Autodesk Inventor part; units mm, degrees
(part 2 of 2)
  line L501 (103.0341, -6.3552) -> (95.8923, 0.7866)
  line L502 (-87.0362, -54.297) -> (-79.8944, -61.4388)
  line L503 (-79.8944, -61.4388) -> (-72.7527, -54.297)
  line L504 (-79.8944, -47.1552) -> (-87.0362, -54.297)
  line L505 (-72.7527, -54.297) -> (-79.8944, -47.1552)
  line L506 (-79.0459, -46.3067) -> (-71.9041, -53.4485)
  line L507 (-71.9041, -53.4485) -> (-64.7624, -46.3067)
  line L508 (-71.9041, -39.1649) -> (-79.0459, -46.3067)
  line L509 (-64.7624, -46.3067) -> (-71.9041, -39.1649)
  line L510 (-71.0556, -38.3164) -> (-63.9138, -45.4582)
  line L511 (-63.9138, -45.4582) -> (-56.7721, -38.3164)
  line L512 (-63.9138, -31.1746) -> (-71.0556, -38.3164)
  line L513 (-56.7721, -38.3164) -> (-63.9138, -31.1746)
  line L514 (-63.0653, -30.3261) -> (-55.9235, -37.4679)
  line L515 (-55.9235, -37.4679) -> (-48.7817, -30.3261)
  line L516 (-55.9235, -23.1843) -> (-63.0653, -30.3261)
  line L517 (-48.7817, -30.3261) -> (-55.9235, -23.1843)
  line L518 (-55.075, -22.3358) -> (-47.9332, -29.4775)
  line L519 (-47.9332, -29.4775) -> (-40.7914, -22.3358)
  line L520 (-47.9332, -15.194) -> (-55.075, -22.3358)
  line L521 (-40.7914, -22.3358) -> (-47.9332, -15.194)
  line L522 (-47.0847, -14.3455) -> (-39.9429, -21.4872)
  line L523 (-39.9429, -21.4872) -> (-32.8011, -14.3455)
  line L524 (-39.9429, -7.2037) -> (-47.0847, -14.3455)
  line L525 (-32.8011, -14.3455) -> (-39.9429, -7.2037)
  line L526 (-39.0944, -6.3552) -> (-31.9526, -13.4969)
  line L527 (-31.9526, -13.4969) -> (-24.8108, -6.3552)
  line L528 (-31.9526, 0.7866) -> (-39.0944, -6.3552)
  line L529 (-24.8108, -6.3552) -> (-31.9526, 0.7866)
  line L530 (-31.1041, 1.6352) -> (-23.9623, -5.5066)
  line L531 (-23.9623, -5.5066) -> (-16.8205, 1.6352)
  line L532 (-23.9623, 8.7769) -> (-31.1041, 1.6352)
  line L533 (-16.8205, 1.6352) -> (-23.9623, 8.7769)
  line L534 (-23.1138, 9.6255) -> (-15.972, 2.4837)
  line L535 (-15.972, 2.4837) -> (-8.8302, 9.6255)
  line L536 (-15.972, 16.7672) -> (-23.1138, 9.6255)
  line L537 (-8.8302, 9.6255) -> (-15.972, 16.7672)
  line L538 (-15.1235, 17.6158) -> (-7.9817, 10.474)
  line L539 (-7.9817, 10.474) -> (-0.8399, 17.6158)
  line L540 (-7.9817, 24.7575) -> (-15.1235, 17.6158)
  line L541 (-0.8399, 17.6158) -> (-7.9817, 24.7575)
  line L542 (-7.1332, 25.6061) -> (0.0086, 18.4643)
  line L543 (0.0086, 18.4643) -> (7.1504, 25.6061)
  line L544 (0.0086, 32.7478) -> (-7.1332, 25.6061)
  line L545 (7.1504, 25.6061) -> (0.0086, 32.7478)
  line L546 (0.8571, 33.5964) -> (7.9989, 26.4546)
  line L547 (7.9989, 26.4546) -> (15.1407, 33.5964)
  line L548 (7.9989, 40.7382) -> (0.8571, 33.5964)
  line L549 (15.1407, 33.5964) -> (7.9989, 40.7382)
  line L550 (8.8475, 41.5867) -> (15.9892, 34.4449)
  line L551 (15.9892, 34.4449) -> (23.131, 41.5867)
  line L552 (15.9892, 48.7285) -> (8.8475, 41.5867)
  line L553 (23.131, 41.5867) -> (15.9892, 48.7285)
  line L554 (16.8378, 49.577) -> (23.9795, 42.4352)
  line L555 (23.9795, 42.4352) -> (31.1213, 49.577)
  line L556 (23.9795, 56.7188) -> (16.8378, 49.577)
  line L557 (31.1213, 49.577) -> (23.9795, 56.7188)
  line L558 (24.8281, 57.5673) -> (31.9698, 50.4255)
  line L559 (31.9698, 50.4255) -> (39.1116, 57.5673)
  line L560 (31.9698, 64.7091) -> (24.8281, 57.5673)
  line L561 (39.1116, 57.5673) -> (31.9698, 64.7091)
  line L562 (-15.1235, -126.2098) -> (-7.9817, -133.3515)
  line L563 (-7.9817, -133.3515) -> (-0.8399, -126.2098)
  line L564 (-7.9817, -119.068) -> (-15.1235, -126.2098)
  line L565 (-0.8399, -126.2098) -> (-7.9817, -119.068)
  line L566 (-7.1332, -118.2194) -> (0.0086, -125.3612)
  line L567 (0.0086, -125.3612) -> (7.1504, -118.2194)
  line L568 (0.0086, -111.0777) -> (-7.1332, -118.2194)
  line L569 (7.1504, -118.2194) -> (0.0086, -111.0777)
  line L570 (0.8571, -110.2291) -> (7.9989, -117.3709)
  line L571 (7.9989, -117.3709) -> (15.1407, -110.2291)
  line L572 (7.9989, -103.0874) -> (0.8571, -110.2291)
  line L573 (15.1407, -110.2291) -> (7.9989, -103.0874)
  line L574 (8.8475, -102.2388) -> (15.9892, -109.3806)
  line L575 (15.9892, -109.3806) -> (23.131, -102.2388)
  line L576 (15.9892, -95.0971) -> (8.8475, -102.2388)
  line L577 (23.131, -102.2388) -> (15.9892, -95.0971)
  line L578 (16.8378, -94.2485) -> (23.9795, -101.3903)
  line L579 (23.9795, -101.3903) -> (31.1213, -94.2485)
  line L580 (23.9795, -87.1067) -> (16.8378, -94.2485)
  line L581 (31.1213, -94.2485) -> (23.9795, -87.1067)
  line L582 (24.8281, -86.2582) -> (31.9698, -93.4)
  line L583 (31.9698, -93.4) -> (39.1116, -86.2582)
  line L584 (31.9698, -79.1164) -> (24.8281, -86.2582)
  line L585 (39.1116, -86.2582) -> (31.9698, -79.1164)
  line L586 (32.8184, -78.2679) -> (39.9602, -85.4097)
  line L587 (39.9602, -85.4097) -> (47.1019, -78.2679)
  line L588 (39.9602, -71.1261) -> (32.8184, -78.2679)
  line L589 (47.1019, -78.2679) -> (39.9602, -71.1261)
  line L590 (40.8087, -70.2776) -> (47.9505, -77.4194)
  line L591 (47.9505, -77.4194) -> (55.0922, -70.2776)
  line L592 (47.9505, -63.1358) -> (40.8087, -70.2776)
  line L593 (55.0922, -70.2776) -> (47.9505, -63.1358)
  line L594 (48.799, -62.2873) -> (55.9408, -69.4291)
  line L595 (55.9408, -69.4291) -> (63.0825, -62.2873)
  line L596 (55.9408, -55.1455) -> (48.799, -62.2873)
  line L597 (63.0825, -62.2873) -> (55.9408, -55.1455)
  line L598 (56.7893, -54.297) -> (63.9311, -61.4388)
  line L599 (63.9311, -61.4388) -> (71.0728, -54.297)
  line L600 (63.9311, -47.1552) -> (56.7893, -54.297)
  line L601 (71.0728, -54.297) -> (63.9311, -47.1552)
  line L602 (64.7796, -46.3067) -> (71.9214, -53.4485)
  line L603 (71.9214, -53.4485) -> (79.0632, -46.3067)
  line L604 (71.9214, -39.1649) -> (64.7796, -46.3067)
  line L605 (79.0632, -46.3067) -> (71.9214, -39.1649)
  line L606 (72.7699, -38.3164) -> (79.9117, -45.4582)
  line L607 (79.9117, -45.4582) -> (87.0535, -38.3164)
  line L608 (79.9117, -31.1746) -> (72.7699, -38.3164)
  line L609 (87.0535, -38.3164) -> (79.9117, -31.1746)
  line L610 (80.7602, -30.3261) -> (87.902, -37.4679)
  line L611 (87.902, -37.4679) -> (95.0438, -30.3261)
  line L612 (87.902, -23.1843) -> (80.7602, -30.3261)
  line L613 (95.0438, -30.3261) -> (87.902, -23.1843)
  line L614 (88.7505, -22.3358) -> (95.8923, -29.4775)
  line L615 (95.8923, -29.4775) -> (103.0341, -22.3358)
  line L616 (95.8923, -15.194) -> (88.7505, -22.3358)
  line L617 (103.0341, -22.3358) -> (95.8923, -15.194)
  line L618 (96.7408, -14.3455) -> (103.8826, -21.4872)
  line L619 (103.8826, -21.4872) -> (111.0244, -14.3455)
  line L620 (103.8826, -7.2037) -> (96.7408, -14.3455)
  line L621 (111.0244, -14.3455) -> (103.8826, -7.2037)
  line L622 (-95.0265, -46.3067) -> (-87.8848, -53.4485)
  line L623 (-87.8848, -53.4485) -> (-80.743, -46.3067)
  line L624 (-87.8848, -39.1649) -> (-95.0265, -46.3067)
  line L625 (-80.743, -46.3067) -> (-87.8848, -39.1649)
  line L626 (-87.0362, -38.3164) -> (-79.8944, -45.4582)
  line L627 (-79.8944, -45.4582) -> (-72.7527, -38.3164)
  line L628 (-79.8944, -31.1746) -> (-87.0362, -38.3164)
  line L629 (-72.7527, -38.3164) -> (-79.8944, -31.1746)
  line L630 (-79.0459, -30.3261) -> (-71.9041, -37.4679)
  line L631 (-71.9041, -37.4679) -> (-64.7624, -30.3261)
  line L632 (-71.9041, -23.1843) -> (-79.0459, -30.3261)
  line L633 (-64.7624, -30.3261) -> (-71.9041, -23.1843)
  line L634 (-71.0556, -22.3358) -> (-63.9138, -29.4775)
  line L635 (-63.9138, -29.4775) -> (-56.7721, -22.3358)
  line L636 (-63.9138, -15.194) -> (-71.0556, -22.3358)
  line L637 (-56.7721, -22.3358) -> (-63.9138, -15.194)
  line L638 (-63.0653, -14.3455) -> (-55.9235, -21.4872)
  line L639 (-55.9235, -21.4872) -> (-48.7817, -14.3455)
  line L640 (-55.9235, -7.2037) -> (-63.0653, -14.3455)
  line L641 (-48.7817, -14.3455) -> (-55.9235, -7.2037)
  line L642 (-55.075, -6.3552) -> (-47.9332, -13.4969)
  line L643 (-47.9332, -13.4969) -> (-40.7914, -6.3552)
  line L644 (-47.9332, 0.7866) -> (-55.075, -6.3552)
  line L645 (-40.7914, -6.3552) -> (-47.9332, 0.7866)
  line L646 (-47.0847, 1.6352) -> (-39.9429, -5.5066)
  line L647 (-39.9429, -5.5066) -> (-32.8011, 1.6352)
  line L648 (-39.9429, 8.7769) -> (-47.0847, 1.6352)
  line L649 (-32.8011, 1.6352) -> (-39.9429, 8.7769)
  line L650 (-39.0944, 9.6255) -> (-31.9526, 2.4837)
  line L651 (-31.9526, 2.4837) -> (-24.8108, 9.6255)
  line L652 (-31.9526, 16.7672) -> (-39.0944, 9.6255)
  line L653 (-24.8108, 9.6255) -> (-31.9526, 16.7672)
  line L654 (-31.1041, 17.6158) -> (-23.9623, 10.474)
  line L655 (-23.9623, 10.474) -> (-16.8205, 17.6158)
  line L656 (-23.9623, 24.7575) -> (-31.1041, 17.6158)
  line L657 (-16.8205, 17.6158) -> (-23.9623, 24.7575)
  line L658 (-23.1138, 25.6061) -> (-15.972, 18.4643)
  line L659 (-15.972, 18.4643) -> (-8.8302, 25.6061)
  line L660 (-15.972, 32.7478) -> (-23.1138, 25.6061)
  line L661 (-8.8302, 25.6061) -> (-15.972, 32.7478)
  line L662 (-15.1235, 33.5964) -> (-7.9817, 26.4546)
  line L663 (-7.9817, 26.4546) -> (-0.8399, 33.5964)
  line L664 (-7.9817, 40.7382) -> (-15.1235, 33.5964)
  line L665 (-0.8399, 33.5964) -> (-7.9817, 40.7382)
  line L666 (-7.1332, 41.5867) -> (0.0086, 34.4449)
  line L667 (0.0086, 34.4449) -> (7.1504, 41.5867)
  line L668 (0.0086, 48.7285) -> (-7.1332, 41.5867)
  line L669 (7.1504, 41.5867) -> (0.0086, 48.7285)
  line L670 (0.8571, 49.577) -> (7.9989, 42.4352)
  line L671 (7.9989, 42.4352) -> (15.1407, 49.577)
  line L672 (7.9989, 56.7188) -> (0.8571, 49.577)
  line L673 (15.1407, 49.577) -> (7.9989, 56.7188)
  line L674 (8.8475, 57.5673) -> (15.9892, 50.4255)
  line L675 (15.9892, 50.4255) -> (23.131, 57.5673)
  line L676 (15.9892, 64.7091) -> (8.8475, 57.5673)
  line L677 (23.131, 57.5673) -> (15.9892, 64.7091)
  line L678 (16.8378, 65.5576) -> (23.9795, 58.4158)
  line L679 (23.9795, 58.4158) -> (31.1213, 65.5576)
  line L680 (23.9795, 72.6994) -> (16.8378, 65.5576)
  line L681 (31.1213, 65.5576) -> (23.9795, 72.6994)
  line L682 (-7.1332, -134.2001) -> (0.0086, -141.3418)
  line L683 (0.0086, -141.3418) -> (7.1504, -134.2001)
  line L684 (0.0086, -127.0583) -> (-7.1332, -134.2001)
  line L685 (7.1504, -134.2001) -> (0.0086, -127.0583)
  line L686 (0.8571, -126.2098) -> (7.9989, -133.3515)
  line L687 (7.9989, -133.3515) -> (15.1407, -126.2098)
  line L688 (7.9989, -119.068) -> (0.8571, -126.2098)
  line L689 (15.1407, -126.2098) -> (7.9989, -119.068)
  line L690 (8.8475, -118.2194) -> (15.9892, -125.3612)
  line L691 (15.9892, -125.3612) -> (23.131, -118.2194)
  line L692 (15.9892, -111.0777) -> (8.8475, -118.2194)
  line L693 (23.131, -118.2194) -> (15.9892, -111.0777)
  line L694 (16.8378, -110.2291) -> (23.9795, -117.3709)
  line L695 (23.9795, -117.3709) -> (31.1213, -110.2291)
  line L696 (23.9795, -103.0874) -> (16.8378, -110.2291)
  line L697 (31.1213, -110.2291) -> (23.9795, -103.0874)
  line L698 (24.8281, -102.2388) -> (31.9698, -109.3806)
  line L699 (31.9698, -109.3806) -> (39.1116, -102.2388)
  line L700 (31.9698, -95.0971) -> (24.8281, -102.2388)
  line L701 (39.1116, -102.2388) -> (31.9698, -95.0971)
  line L702 (32.8184, -94.2485) -> (39.9602, -101.3903)
  line L703 (39.9602, -101.3903) -> (47.1019, -94.2485)
  line L704 (39.9602, -87.1067) -> (32.8184, -94.2485)
  line L705 (47.1019, -94.2485) -> (39.9602, -87.1067)
  line L706 (40.8087, -86.2582) -> (47.9505, -93.4)
  line L707 (47.9505, -93.4) -> (55.0922, -86.2582)
  line L708 (47.9505, -79.1164) -> (40.8087, -86.2582)
  line L709 (55.0922, -86.2582) -> (47.9505, -79.1164)
  line L710 (48.799, -78.2679) -> (55.9408, -85.4097)
  line L711 (55.9408, -85.4097) -> (63.0825, -78.2679)
  line L712 (55.9408, -71.1261) -> (48.799, -78.2679)
  line L713 (63.0825, -78.2679) -> (55.9408, -71.1261)
  line L714 (56.7893, -70.2776) -> (63.9311, -77.4194)
  line L715 (63.9311, -77.4194) -> (71.0728, -70.2776)
  line L716 (63.9311, -63.1358) -> (56.7893, -70.2776)
  line L717 (71.0728, -70.2776) -> (63.9311, -63.1358)
  line L718 (64.7796, -62.2873) -> (71.9214, -69.4291)
  line L719 (71.9214, -69.4291) -> (79.0632, -62.2873)
  line L720 (71.9214, -55.1455) -> (64.7796, -62.2873)
  line L721 (79.0632, -62.2873) -> (71.9214, -55.1455)
  line L722 (72.7699, -54.297) -> (79.9117, -61.4388)
  line L723 (79.9117, -61.4388) -> (87.0535, -54.297)
  line L724 (79.9117, -47.1552) -> (72.7699, -54.297)
  line L725 (87.0535, -54.297) -> (79.9117, -47.1552)
  line L726 (80.7602, -46.3067) -> (87.902, -53.4485)
  line L727 (87.902, -53.4485) -> (95.0438, -46.3067)
  line L728 (87.902, -39.1649) -> (80.7602, -46.3067)
  line L729 (95.0438, -46.3067) -> (87.902, -39.1649)
  line L730 (88.7505, -38.3164) -> (95.8923, -45.4582)
  line L731 (95.8923, -45.4582) -> (103.0341, -38.3164)
  line L732 (95.8923, -31.1746) -> (88.7505, -38.3164)
  line L733 (103.0341, -38.3164) -> (95.8923, -31.1746)
  line L734 (96.7408, -30.3261) -> (103.8826, -37.4679)
  line L735 (103.8826, -37.4679) -> (111.0244, -30.3261)
  line L736 (103.8826, -23.1843) -> (96.7408, -30.3261)
  line L737 (111.0244, -30.3261) -> (103.8826, -23.1843)
  line L738 (104.7311, -22.3358) -> (111.8729, -29.4775)
  line L739 (111.8729, -29.4775) -> (119.0147, -22.3358)
  line L740 (111.8729, -15.194) -> (104.7311, -22.3358)
  line L741 (119.0147, -22.3358) -> (111.8729, -15.194)
  line L742 (-103.0168, -38.3164) -> (-95.8751, -45.4582)
  line L743 (-95.8751, -45.4582) -> (-88.7333, -38.3164)
  line L744 (-95.8751, -31.1746) -> (-103.0168, -38.3164)
  line L745 (-88.7333, -38.3164) -> (-95.8751, -31.1746)
  line L746 (-95.0265, -30.3261) -> (-87.8848, -37.4679)
  line L747 (-87.8848, -37.4679) -> (-80.743, -30.3261)
  line L748 (-87.8848, -23.1843) -> (-95.0265, -30.3261)
  line L749 (-80.743, -30.3261) -> (-87.8848, -23.1843)
  line L750 (-87.0362, -22.3358) -> (-79.8944, -29.4775)
  line L751 (-79.8944, -29.4775) -> (-72.7527, -22.3358)
  line L752 (-79.8944, -15.194) -> (-87.0362, -22.3358)
  line L753 (-72.7527, -22.3358) -> (-79.8944, -15.194)
  line L754 (-79.0459, -14.3455) -> (-71.9041, -21.4872)
  line L755 (-71.9041, -21.4872) -> (-64.7624, -14.3455)
  line L756 (-71.9041, -7.2037) -> (-79.0459, -14.3455)
  line L757 (-64.7624, -14.3455) -> (-71.9041, -7.2037)
  line L758 (-71.0556, -6.3552) -> (-63.9138, -13.4969)
  line L759 (-63.9138, -13.4969) -> (-56.7721, -6.3552)
  line L760 (-63.9138, 0.7866) -> (-71.0556, -6.3552)
  line L761 (-56.7721, -6.3552) -> (-63.9138, 0.7866)
  line L762 (-63.0653, 1.6352) -> (-55.9235, -5.5066)
  line L763 (-55.9235, -5.5066) -> (-48.7817, 1.6352)
  line L764 (-55.9235, 8.7769) -> (-63.0653, 1.6352)
  line L765 (-48.7817, 1.6352) -> (-55.9235, 8.7769)
  line L766 (-55.075, 9.6255) -> (-47.9332, 2.4837)
  line L767 (-47.9332, 2.4837) -> (-40.7914, 9.6255)
  line L768 (-47.9332, 16.7672) -> (-55.075, 9.6255)
  line L769 (-40.7914, 9.6255) -> (-47.9332, 16.7672)
  line L770 (-47.0847, 17.6158) -> (-39.9429, 10.474)
  line L771 (-39.9429, 10.474) -> (-32.8011, 17.6158)
  line L772 (-39.9429, 24.7575) -> (-47.0847, 17.6158)
  line L773 (-32.8011, 17.6158) -> (-39.9429, 24.7575)
  line L774 (-39.0944, 25.6061) -> (-31.9526, 18.4643)
  line L775 (-31.9526, 18.4643) -> (-24.8108, 25.6061)
  line L776 (-31.9526, 32.7478) -> (-39.0944, 25.6061)
  line L777 (-24.8108, 25.6061) -> (-31.9526, 32.7478)
  line L778 (-31.1041, 33.5964) -> (-23.9623, 26.4546)
  line L779 (-23.9623, 26.4546) -> (-16.8205, 33.5964)
  line L780 (-23.9623, 40.7382) -> (-31.1041, 33.5964)
  line L781 (-16.8205, 33.5964) -> (-23.9623, 40.7382)
  line L782 (-23.1138, 41.5867) -> (-15.972, 34.4449)
  line L783 (-15.972, 34.4449) -> (-8.8302, 41.5867)
  line L784 (-15.972, 48.7285) -> (-23.1138, 41.5867)
  line L785 (-8.8302, 41.5867) -> (-15.972, 48.7285)
  line L786 (-15.1235, 49.577) -> (-7.9817, 42.4352)
  line L787 (-7.9817, 42.4352) -> (-0.8399, 49.577)
  line L788 (-7.9817, 56.7188) -> (-15.1235, 49.577)
  line L789 (-0.8399, 49.577) -> (-7.9817, 56.7188)
  line L790 (-7.1332, 57.5673) -> (0.0086, 50.4255)
  line L791 (0.0086, 50.4255) -> (7.1504, 57.5673)
  line L792 (0.0086, 64.7091) -> (-7.1332, 57.5673)
  line L793 (7.1504, 57.5673) -> (0.0086, 64.7091)
  line L794 (0.8571, 65.5576) -> (7.9989, 58.4158)
  line L795 (7.9989, 58.4158) -> (15.1407, 65.5576)
  line L796 (7.9989, 72.6994) -> (0.8571, 65.5576)
  line L797 (15.1407, 65.5576) -> (7.9989, 72.6994)
  line L798 (8.8475, 73.5479) -> (15.9892, 66.4061)
  line L799 (15.9892, 66.4061) -> (23.131, 73.5479)
  line L800 (15.9892, 80.6897) -> (8.8475, 73.5479)
  line L801 (23.131, 73.5479) -> (15.9892, 80.6897)
  line L802 (0.8571, -142.1904) -> (7.9989, -149.3321)
  line L803 (7.9989, -149.3321) -> (15.1407, -142.1904)
  line L804 (7.9989, -135.0486) -> (0.8571, -142.1904)
  line L805 (15.1407, -142.1904) -> (7.9989, -135.0486)
  line L806 (8.8475, -134.2001) -> (15.9892, -141.3418)
  line L807 (15.9892, -141.3418) -> (23.131, -134.2001)
  line L808 (15.9892, -127.0583) -> (8.8475, -134.2001)
  line L809 (23.131, -134.2001) -> (15.9892, -127.0583)
  line L810 (16.8378, -126.2098) -> (23.9795, -133.3515)
  line L811 (23.9795, -133.3515) -> (31.1213, -126.2098)
  line L812 (23.9795, -119.068) -> (16.8378, -126.2098)
  line L813 (31.1213, -126.2098) -> (23.9795, -119.068)
  line L814 (24.8281, -118.2194) -> (31.9698, -125.3612)
  line L815 (31.9698, -125.3612) -> (39.1116, -118.2194)
  line L816 (31.9698, -111.0777) -> (24.8281, -118.2194)
  line L817 (39.1116, -118.2194) -> (31.9698, -111.0777)
  line L818 (32.8184, -110.2291) -> (39.9602, -117.3709)
  line L819 (39.9602, -117.3709) -> (47.1019, -110.2291)
  line L820 (39.9602, -103.0874) -> (32.8184, -110.2291)
  line L821 (47.1019, -110.2291) -> (39.9602, -103.0874)
  line L822 (40.8087, -102.2388) -> (47.9505, -109.3806)
  line L823 (47.9505, -109.3806) -> (55.0922, -102.2388)
  line L824 (47.9505, -95.0971) -> (40.8087, -102.2388)
  line L825 (55.0922, -102.2388) -> (47.9505, -95.0971)
  line L826 (48.799, -94.2485) -> (55.9408, -101.3903)
  line L827 (55.9408, -101.3903) -> (63.0825, -94.2485)
  line L828 (55.9408, -87.1067) -> (48.799, -94.2485)
  line L829 (63.0825, -94.2485) -> (55.9408, -87.1067)
  line L830 (56.7893, -86.2582) -> (63.9311, -93.4)
  line L831 (63.9311, -93.4) -> (71.0728, -86.2582)
  line L832 (63.9311, -79.1164) -> (56.7893, -86.2582)
  line L833 (71.0728, -86.2582) -> (63.9311, -79.1164)
  line L834 (64.7796, -78.2679) -> (71.9214, -85.4097)
  line L835 (71.9214, -85.4097) -> (79.0632, -78.2679)
  line L836 (71.9214, -71.1261) -> (64.7796, -78.2679)
  line L837 (79.0632, -78.2679) -> (71.9214, -71.1261)
  line L838 (72.7699, -70.2776) -> (79.9117, -77.4194)
  line L839 (79.9117, -77.4194) -> (87.0535, -70.2776)
  line L840 (79.9117, -63.1358) -> (72.7699, -70.2776)
  line L841 (87.0535, -70.2776) -> (79.9117, -63.1358)
  line L842 (80.7602, -62.2873) -> (87.902, -69.4291)
  line L843 (87.902, -69.4291) -> (95.0438, -62.2873)
  line L844 (87.902, -55.1455) -> (80.7602, -62.2873)
  line L845 (95.0438, -62.2873) -> (87.902, -55.1455)
  line L846 (88.7505, -54.297) -> (95.8923, -61.4388)
  line L847 (95.8923, -61.4388) -> (103.0341, -54.297)
  line L848 (95.8923, -47.1552) -> (88.7505, -54.297)
  line L849 (103.0341, -54.297) -> (95.8923, -47.1552)
  line L850 (96.7408, -46.3067) -> (103.8826, -53.4485)
  line L851 (103.8826, -53.4485) -> (111.0244, -46.3067)
  line L852 (103.8826, -39.1649) -> (96.7408, -46.3067)
  line L853 (111.0244, -46.3067) -> (103.8826, -39.1649)
  line L854 (104.7311, -38.3164) -> (111.8729, -45.4582)
  line L855 (111.8729, -45.4582) -> (119.0147, -38.3164)
  line L856 (111.8729, -31.1746) -> (104.7311, -38.3164)
  line L857 (119.0147, -38.3164) -> (111.8729, -31.1746)
  line L858 (112.7214, -30.3261) -> (119.8632, -37.4679)
  line L859 (119.8632, -37.4679) -> (127.005, -30.3261)
  line L860 (119.8632, -23.1843) -> (112.7214, -30.3261)
  line L861 (127.005, -30.3261) -> (119.8632, -23.1843)
  line L862 (-111.0071, -30.3261) -> (-103.8654, -37.4679)
  line L863 (-103.8654, -37.4679) -> (-96.7236, -30.3261)
  line L864 (-103.8654, -23.1843) -> (-111.0071, -30.3261)
  line L865 (-96.7236, -30.3261) -> (-103.8654, -23.1843)
  line L866 (-103.0168, -22.3358) -> (-95.8751, -29.4775)
  line L867 (-95.8751, -29.4775) -> (-88.7333, -22.3358)
  line L868 (-95.8751, -15.194) -> (-103.0168, -22.3358)
  line L869 (-88.7333, -22.3358) -> (-95.8751, -15.194)
  line L870 (-95.0265, -14.3455) -> (-87.8848, -21.4872)
  line L871 (-87.8848, -21.4872) -> (-80.743, -14.3455)
  line L872 (-87.8848, -7.2037) -> (-95.0265, -14.3455)
  line L873 (-80.743, -14.3455) -> (-87.8848, -7.2037)
  line L874 (-87.0362, -6.3552) -> (-79.8944, -13.4969)
  line L875 (-79.8944, -13.4969) -> (-72.7527, -6.3552)
  line L876 (-79.8944, 0.7866) -> (-87.0362, -6.3552)
  line L877 (-72.7527, -6.3552) -> (-79.8944, 0.7866)
  line L878 (-79.0459, 1.6352) -> (-71.9041, -5.5066)
  line L879 (-71.9041, -5.5066) -> (-64.7624, 1.6352)
  line L880 (-71.9041, 8.7769) -> (-79.0459, 1.6352)
  line L881 (-64.7624, 1.6352) -> (-71.9041, 8.7769)
  line L882 (-71.0556, 9.6255) -> (-63.9138, 2.4837)
  line L883 (-63.9138, 2.4837) -> (-56.7721, 9.6255)
  line L884 (-63.9138, 16.7672) -> (-71.0556, 9.6255)
  line L885 (-56.7721, 9.6255) -> (-63.9138, 16.7672)
  line L886 (-63.0653, 17.6158) -> (-55.9235, 10.474)
  line L887 (-55.9235, 10.474) -> (-48.7817, 17.6158)
  line L888 (-55.9235, 24.7575) -> (-63.0653, 17.6158)
  line L889 (-48.7817, 17.6158) -> (-55.9235, 24.7575)
  line L890 (-55.075, 25.6061) -> (-47.9332, 18.4643)
  line L891 (-47.9332, 18.4643) -> (-40.7914, 25.6061)
  line L892 (-47.9332, 32.7478) -> (-55.075, 25.6061)
  line L893 (-40.7914, 25.6061) -> (-47.9332, 32.7478)
  line L894 (-47.0847, 33.5964) -> (-39.9429, 26.4546)
  line L895 (-39.9429, 26.4546) -> (-32.8011, 33.5964)
  line L896 (-39.9429, 40.7382) -> (-47.0847, 33.5964)
  line L897 (-32.8011, 33.5964) -> (-39.9429, 40.7382)
  line L898 (-39.0944, 41.5867) -> (-31.9526, 34.4449)
  line L899 (-31.9526, 34.4449) -> (-24.8108, 41.5867)
  line L900 (-31.9526, 48.7285) -> (-39.0944, 41.5867)
  line L901 (-24.8108, 41.5867) -> (-31.9526, 48.7285)
  line L902 (-31.1041, 49.577) -> (-23.9623, 42.4352)
  line L903 (-23.9623, 42.4352) -> (-16.8205, 49.577)
  line L904 (-23.9623, 56.7188) -> (-31.1041, 49.577)
  line L905 (-16.8205, 49.577) -> (-23.9623, 56.7188)
  line L906 (-23.1138, 57.5673) -> (-15.972, 50.4255)
  line L907 (-15.972, 50.4255) -> (-8.8302, 57.5673)
  line L908 (-15.972, 64.7091) -> (-23.1138, 57.5673)
  line L909 (-8.8302, 57.5673) -> (-15.972, 64.7091)
  line L910 (-15.1235, 65.5576) -> (-7.9817, 58.4158)
  line L911 (-7.9817, 58.4158) -> (-0.8399, 65.5576)
  line L912 (-7.9817, 72.6994) -> (-15.1235, 65.5576)
  line L913 (-0.8399, 65.5576) -> (-7.9817, 72.6994)
  line L914 (-7.1332, 73.5479) -> (0.0086, 66.4061)
  line L915 (0.0086, 66.4061) -> (7.1504, 73.5479)
  line L916 (0.0086, 80.6897) -> (-7.1332, 73.5479)
  line L917 (7.1504, 73.5479) -> (0.0086, 80.6897)
  line L918 (0.8571, 81.5382) -> (7.9989, 74.3964)
  line L919 (7.9989, 74.3964) -> (15.1407, 81.5382)
  line L920 (7.9989, 88.68) -> (0.8571, 81.5382)
  line L921 (15.1407, 81.5382) -> (7.9989, 88.68)
  line L922 (8.8475, -150.1807) -> (15.9892, -157.3225)
  line L923 (15.9892, -157.3225) -> (23.131, -150.1807)
  line L924 (15.9892, -143.0389) -> (8.8475, -150.1807)
  line L925 (23.131, -150.1807) -> (15.9892, -143.0389)
  line L926 (16.8378, -142.1904) -> (23.9795, -149.3321)
  line L927 (23.9795, -149.3321) -> (31.1213, -142.1904)
  line L928 (23.9795, -135.0486) -> (16.8378, -142.1904)
  line L929 (31.1213, -142.1904) -> (23.9795, -135.0486)
  line L930 (24.8281, -134.2001) -> (31.9698, -141.3418)
  line L931 (31.9698, -141.3418) -> (39.1116, -134.2001)
  line L932 (31.9698, -127.0583) -> (24.8281, -134.2001)
  line L933 (39.1116, -134.2001) -> (31.9698, -127.0583)
  line L934 (32.8184, -126.2098) -> (39.9602, -133.3515)
  line L935 (39.9602, -133.3515) -> (47.1019, -126.2098)
  line L936 (39.9602, -119.068) -> (32.8184, -126.2098)
  line L937 (47.1019, -126.2098) -> (39.9602, -119.068)
  line L938 (40.8087, -118.2194) -> (47.9505, -125.3612)
  line L939 (47.9505, -125.3612) -> (55.0922, -118.2194)
  line L940 (47.9505, -111.0777) -> (40.8087, -118.2194)
  line L941 (55.0922, -118.2194) -> (47.9505, -111.0777)
  line L942 (48.799, -110.2291) -> (55.9408, -117.3709)
  line L943 (55.9408, -117.3709) -> (63.0825, -110.2291)
  line L944 (55.9408, -103.0874) -> (48.799, -110.2291)
  line L945 (63.0825, -110.2291) -> (55.9408, -103.0874)
  line L946 (56.7893, -102.2388) -> (63.9311, -109.3806)
  line L947 (63.9311, -109.3806) -> (71.0728, -102.2388)
  line L948 (63.9311, -95.0971) -> (56.7893, -102.2388)
  line L949 (71.0728, -102.2388) -> (63.9311, -95.0971)
  line L950 (64.7796, -94.2485) -> (71.9214, -101.3903)
  line L951 (71.9214, -101.3903) -> (79.0632, -94.2485)
  line L952 (71.9214, -87.1067) -> (64.7796, -94.2485)
  line L953 (79.0632, -94.2485) -> (71.9214, -87.1067)
  line L954 (72.7699, -86.2582) -> (79.9117, -93.4)
  line L955 (79.9117, -93.4) -> (87.0535, -86.2582)
  line L956 (79.9117, -79.1164) -> (72.7699, -86.2582)
  line L957 (87.0535, -86.2582) -> (79.9117, -79.1164)
  line L958 (80.7602, -78.2679) -> (87.902, -85.4097)
  line L959 (87.902, -85.4097) -> (95.0438, -78.2679)
  line L960 (87.902, -71.1261) -> (80.7602, -78.2679)
  line L961 (95.0438, -78.2679) -> (87.902, -71.1261)
  line L962 (88.7505, -70.2776) -> (95.8923, -77.4194)
  line L963 (95.8923, -77.4194) -> (103.0341, -70.2776)
  line L964 (95.8923, -63.1358) -> (88.7505, -70.2776)
  line L965 (103.0341, -70.2776) -> (95.8923, -63.1358)
  line L966 (96.7408, -62.2873) -> (103.8826, -69.4291)
  line L967 (103.8826, -69.4291) -> (111.0244, -62.2873)
  line L968 (103.8826, -55.1455) -> (96.7408, -62.2873)
  line L969 (111.0244, -62.2873) -> (103.8826, -55.1455)
  line L970 (104.7311, -54.297) -> (111.8729, -61.4388)
  line L971 (111.8729, -61.4388) -> (119.0147, -54.297)
  line L972 (111.8729, -47.1552) -> (104.7311, -54.297)
  line L973 (119.0147, -54.297) -> (111.8729, -47.1552)
  line L974 (112.7214, -46.3067) -> (119.8632, -53.4485)
  line L975 (119.8632, -53.4485) -> (127.005, -46.3067)
  line L976 (119.8632, -39.1649) -> (112.7214, -46.3067)
  line L977 (127.005, -46.3067) -> (119.8632, -39.1649)
  line L978 (120.7117, -38.3164) -> (127.8535, -45.4582)
  line L979 (127.8535, -45.4582) -> (134.9953, -38.3164)
  line L980 (127.8535, -31.1746) -> (120.7117, -38.3164)
  line L981 (134.9953, -38.3164) -> (127.8535, -31.1746)
  line L982 (-118.9975, -22.3358) -> (-111.8557, -29.4775)
  line L983 (-111.8557, -29.4775) -> (-104.7139, -22.3358)
  line L984 (-111.8557, -15.194) -> (-118.9975, -22.3358)
  line L985 (-104.7139, -22.3358) -> (-111.8557, -15.194)
  line L986 (-111.0071, -14.3455) -> (-103.8654, -21.4872)
  line L987 (-103.8654, -21.4872) -> (-96.7236, -14.3455)
  line L988 (-103.8654, -7.2037) -> (-111.0071, -14.3455)
  line L989 (-96.7236, -14.3455) -> (-103.8654, -7.2037)
  line L990 (-103.0168, -6.3552) -> (-95.8751, -13.4969)
  line L991 (-95.8751, -13.4969) -> (-88.7333, -6.3552)
  line L992 (-95.8751, 0.7866) -> (-103.0168, -6.3552)
  line L993 (-88.7333, -6.3552) -> (-95.8751, 0.7866)
  line L994 (-95.0265, 1.6352) -> (-87.8848, -5.5066)
  line L995 (-87.8848, -5.5066) -> (-80.743, 1.6352)
  line L996 (-87.8848, 8.7769) -> (-95.0265, 1.6352)
  line L997 (-80.743, 1.6352) -> (-87.8848, 8.7769)
  line L998 (-87.0362, 9.6255) -> (-79.8944, 2.4837)
  line L999 (-79.8944, 2.4837) -> (-72.7527, 9.6255)
  line L1000 (-79.8944, 16.7672) -> (-87.0362, 9.6255)
  line L1001 (-72.7527, 9.6255) -> (-79.8944, 16.7672)
  line L1002 (-79.0459, 17.6158) -> (-71.9041, 10.474)
  line L1003 (-71.9041, 10.474) -> (-64.7624, 17.6158)
  line L1004 (-71.9041, 24.7575) -> (-79.0459, 17.6158)
  line L1005 (-64.7624, 17.6158) -> (-71.9041, 24.7575)
  line L1006 (-71.0556, 25.6061) -> (-63.9138, 18.4643)
  line L1007 (-63.9138, 18.4643) -> (-56.7721, 25.6061)
  line L1008 (-63.9138, 32.7478) -> (-71.0556, 25.6061)
  line L1009 (-56.7721, 25.6061) -> (-63.9138, 32.7478)
  line L1010 (-63.0653, 33.5964) -> (-55.9235, 26.4546)
  line L1011 (-55.9235, 26.4546) -> (-48.7817, 33.5964)
  line L1012 (-55.9235, 40.7382) -> (-63.0653, 33.5964)
  line L1013 (-48.7817, 33.5964) -> (-55.9235, 40.7382)
  line L1014 (-55.075, 41.5867) -> (-47.9332, 34.4449)
  line L1015 (-47.9332, 34.4449) -> (-40.7914, 41.5867)
  line L1016 (-47.9332, 48.7285) -> (-55.075, 41.5867)
  line L1017 (-40.7914, 41.5867) -> (-47.9332, 48.7285)
  line L1018 (-47.0847, 49.577) -> (-39.9429, 42.4352)
  line L1019 (-39.9429, 42.4352) -> (-32.8011, 49.577)
  line L1020 (-39.9429, 56.7188) -> (-47.0847, 49.577)
  line L1021 (-32.8011, 49.577) -> (-39.9429, 56.7188)
  line L1022 (-39.0944, 57.5673) -> (-31.9526, 50.4255)
  line L1023 (-31.9526, 50.4255) -> (-24.8108, 57.5673)
  line L1024 (-31.9526, 64.7091) -> (-39.0944, 57.5673)
  line L1025 (-24.8108, 57.5673) -> (-31.9526, 64.7091)
  line L1026 (-31.1041, 65.5576) -> (-23.9623, 58.4158)
  line L1027 (-23.9623, 58.4158) -> (-16.8205, 65.5576)
  line L1028 (-23.9623, 72.6994) -> (-31.1041, 65.5576)
  line L1029 (-16.8205, 65.5576) -> (-23.9623, 72.6994)
  line L1030 (-23.1138, 73.5479) -> (-15.972, 66.4061)
  line L1031 (-15.972, 66.4061) -> (-8.8302, 73.5479)
  line L1032 (-15.972, 80.6897) -> (-23.1138, 73.5479)
  line L1033 (-8.8302, 73.5479) -> (-15.972, 80.6897)
  line L1034 (-15.1235, 81.5382) -> (-7.9817, 74.3964)
  line L1035 (-7.9817, 74.3964) -> (-0.8399, 81.5382)
  line L1036 (-7.9817, 88.68) -> (-15.1235, 81.5382)
  line L1037 (-0.8399, 81.5382) -> (-7.9817, 88.68)
  line L1038 (-7.1332, 89.5285) -> (0.0086, 82.3867)
  line L1039 (0.0086, 82.3867) -> (7.1504, 89.5285)
  line L1040 (0.0086, 96.6703) -> (-7.1332, 89.5285)
  line L1041 (7.1504, 89.5285) -> (0.0086, 96.6703)
  line L1042 (-27.6, -18.1164) -> (-27.6, -12.9164) projected
  line L1043 (-27.6, -12.9164) -> (-32.5, -12.9164) projected
  line L1044 (-32.5, -12.9164) -> (-32.5, -18.1164) projected
  line L1045 (-32.5, -18.1164) -> (-27.6, -18.1164) projected
  line L1046 (-32.5, 2.6) -> (-32.5, -2.6) projected
  line L1047 (-32.5, -2.6) -> (-27.6, -2.6) projected
  line L1048 (-27.6, -2.6) -> (-27.6, 2.6) projected
  line L1049 (-27.6, 2.6) -> (-32.5, 2.6) projected
  line L1050 (-32.5, 12.9164) -> (-27.6, 12.9164) projected
  line L1051 (-27.6, 12.9164) -> (-27.6, 18.1164) projected
  line L1052 (-27.6, 18.1164) -> (-32.5, 18.1164) projected
  line L1053 (-32.5, 18.1164) -> (-32.5, 12.9164) projected
  line L1054 (-22.1414, 23.575) -> (-16.9414, 23.575) projected
  line L1055 (-16.9414, 23.575) -> (-16.9414, 28.475) projected
  line L1056 (-16.9414, 28.475) -> (-22.1414, 28.475) projected
  line L1057 (-22.1414, 28.475) -> (-22.1414, 23.575) projected
  line L1058 (-16.9414, -23.575) -> (-22.1414, -23.575) projected
  line L1059 (-22.1414, -23.575) -> (-22.1414, -28.475) projected
  line L1060 (-22.1414, -28.475) -> (-21.5414, -27.875) projected
  line L1061 (-21.5414, -27.875) -> (-21.5414, -24.175) projected
  line L1062 (-21.5414, -24.175) -> (-22.1414, -23.575) projected
  line L1063 (-22.1414, -23.575) -> (-22.1414, -28.475) projected
  line L1064 (-22.1414, -28.475) -> (-16.9414, -28.475) projected
  line L1065 (-16.9414, -28.475) -> (-16.9414, -23.575) projected
  line L1066 (-0.275, -23.575) -> (-0.275, -28.475) projected
  line L1067 (-0.275, -28.475) -> (4.925, -28.475) projected
  line L1068 (4.925, -28.475) -> (4.925, -23.575) projected
  line L1069 (21.5914, -23.575) -> (21.5914, -28.475) projected
  line L1070 (22.1914, -27.875) -> (21.5914, -28.475) projected
  line L1071 (22.1914, -27.875) -> (22.1914, -24.175) projected
  line L1072 (22.1914, -24.175) -> (21.5914, -23.575) projected
  line L1073 (21.5914, -28.475) -> (29.9, -28.475) projected
  line L1074 (29.9, -28.475) -> (29.9, -20.1664) projected
  line L1075 (29.9, -20.1664) -> (25, -20.1664) projected
  line L1076 (25, -2.6) -> (29.9, -2.6) projected
  line L1077 (29.9, -2.6) -> (29.9, 2.6) projected
  line L1078 (29.9, 2.6) -> (25, 2.6) projected
  line L1079 (25, 20.1664) -> (29.9, 20.1664) projected
  line L1080 (29.9, 20.1664) -> (29.9, 28.475) projected
  line L1081 (29.9, 28.475) -> (21.5914, 28.475) projected
  line L1082 (21.5914, 28.475) -> (21.5914, 23.575) projected
  line L1083 (4.925, 23.575) -> (4.925, 28.475) projected
  line L1084 (4.925, 28.475) -> (-0.275, 28.475) projected
  line L1085 (-0.275, 28.475) -> (-0.275, 23.575) projected
  line L1086 (-0.275, 23.575) -> (4.925, 23.575) projected
  point P0 (0, 0)
  point P1 (59.725, 30.2388)
  point P2 (49.9954, 32.4)
  point P3 (48.2983, 32.4)
  point P4 (54.555, 25.0688)
  point P5 (57.9973, 27.097)
  point P6 (59.725, 20.9733)
  point P7 (59.725, 22.6704)
  point P8 (59.725, 28.5418)
  point P9 (14.9999, 17.475)
  point P10 (16.1313, 17.475)
  point P11 (19.3703, 17.0631)
  point P12 (21.5725, 15.9923)
  point P13 (15.6414, 32.4)
  point P14 (13.9443, 32.4)
  point P15 (2.0535, 32.4)
  point P16 (0.3565, 32.4)
  point P17 (18.0341, 32.4)
  point P18 (16.3371, 32.4)
  point P19 (29.9249, 32.4)
  point P20 (31.622, 32.4)
  point P21 (-47.0847, -78.2679)
  point P22 (-39.9429, -85.4097)
  point P23 (-55.075, -84.5612)
  point P24 (-46.9332, -92.4)
  point P25 (-45.2362, -92.4)
  point P26 (-34.6497, -92.4)
  point P27 (-32.9526, -92.4)
  point P28 (-30.9526, -92.4)
  point P29 (-29.2556, -92.4)
  point P30 (-18.6691, -92.4)
  point P31 (-16.972, -92.4)
  point P32 (-14.972, -92.4)
  point P33 (-13.2749, -92.4)
  point P34 (-2.6884, -92.4)
  point P35 (-0.9914, -92.4)
  point P36 (1.0086, -92.4)
  point P37 (2.7057, -92.4)
  point P38 (13.2922, -92.4)
  point P39 (14.9892, -92.4)
  point P40 (16.9892, -92.4)
  point P41 (18.6863, -92.4)
  point P42 (29.2728, -92.4)
  point P43 (30.9698, -92.4)
  point P44 (32.9698, -92.4)
  point P45 (34.6669, -92.4)
  point P46 (45.2534, -92.4)
  point P47 (46.9505, -92.4)
  point P48 (48.9505, -92.4)
  point P49 (50.6475, -92.4)
  point P50 (59.725, -90.891)
  point P51 (59.725, -89.1939)
  point P52 (59.725, -83.3225)
  point P53 (59.725, -81.6255)
  point P54 (54.3541, -74.4098)
  point P55 (55.9848, -72.7791)
  point P56 (59.725, -74.9104)
  point P57 (59.725, -73.2133)
  point P58 (59.725, -67.3419)
  point P59 (59.725, -65.6448)
  point P60 (59.725, -58.9298)
  point P61 (59.725, -57.2327)
  point P62 (59.725, -51.3613)
  point P63 (59.725, -49.6642)
  point P64 (59.725, -42.9491)
  point P65 (59.725, -41.2521)
  point P66 (59.725, -35.3807)
  point P67 (59.725, -33.6836)
  point P68 (59.725, -26.9685)
  point P69 (59.725, -25.2715)
  point P70 (59.725, -19.4001)
  point P71 (59.725, -17.703)
  point P72 (59.725, -10.9879)
  point P73 (59.725, -9.2909)
  point P74 (59.725, -3.4194)
  point P75 (59.725, -1.7224)
  point P76 (59.725, 4.9927)
  point P77 (59.725, 6.6898)
  point P78 (59.725, 12.5612)
  point P79 (59.725, 14.2582)
  point P80 (55.4066, 24.2233)
  point P81 (54.4659, 25.2626)
  point P82 (47.6026, 32.4)
  point P83 (45.9056, 32.4)
  point P84 (34.0148, 32.4)
  point P85 (32.3177, 32.4)
  point P86 (24.9, 12.6648)
  point P87 (24.9, 9.9802)
  point P88 (24.9, -3.5987)
  point P89 (24.9, -6.2832)
  point P90 (9.9867, -23.475)
  point P91 (8.2896, -23.475)
  point P92 (0, -15.2026)
  point P93 (0, -13.2227)
  point P94 (0, -12.3569)
  point P95 (0, -13.4883)
  point P96 (0, 0.778)
  point P97 (0, 3.0407)
  point P98 (0, 3.9065)
  point P99 (0, 2.4923)
  point P100 (1.8464, 17.475)
  point P101 (0.9979, 17.475)
  point P102 (-0.3392, 32.4)
  point P103 (-2.0363, 32.4)
  point P104 (-13.9271, 32.4)
  point P105 (-15.6241, 32.4)
  point P106 (-9.8448, 24.5914)
  point P107 (-7.468, 24.2438)
  point P108 (-8.7177, 24.0215)
  point P109 (-10.3592, 25.4913)
  point P110 (-16.3198, 32.4)
  point P111 (-18.0169, 32.4)
  point P112 (-29.9077, 32.4)
  point P113 (-31.6048, 32.4)
  point P114 (-32.3005, 32.4)
  point P115 (-33.9975, 32.4)
  point P116 (-45.8883, 32.4)
  point P117 (-47.5854, 32.4)
  point P118 (-55.075, 25.6061)
  point P119 (-55.075, 25.6061)
  point P120 (-55.075, 23.909)
  point P121 (-55.075, 11.3225)
  point P122 (-55.075, 9.6255)
  point P123 (-55.075, 9.6255)
  point P124 (-55.075, 7.9284)
  point P125 (-55.075, -4.6581)
  point P126 (-55.075, -6.3552)
  point P127 (-55.075, -6.3552)
  point P128 (-46.3548, -0.7918)
  point P129 (-46.3367, 0.8871)
  point P130 (-38.6534, -4.5)
  point P131 (-41.2324, -4.5)
  point P132 (-55.075, -8.0522)
  point P133 (-55.075, -20.6387)
  point P134 (-55.075, -22.3358)
  point P135 (-55.075, -22.3358)
  point P136 (-55.075, -24.0328)
  point P137 (-55.075, -36.6193)
  point P138 (-55.075, -38.3164)
  point P139 (-55.075, -38.3164)
  point P140 (-55.075, -40.0134)
  point P141 (-55.075, -52.5999)
  point P142 (-55.075, -54.297)
  point P143 (-55.075, -54.297)
  point P144 (-55.075, -55.9941)
  point P145 (-55.075, -68.5806)
  point P146 (-55.075, -70.2776)
  point P147 (-55.075, -70.2776)
  point P148 (-55.075, -71.9747)
  point P149 (42.9337, -74.0997)
  point P150 (43.6573, -73.1263)
  point P151 (46.4487, -75.9177)
  point P152 (45.4753, -76.6413)
  point P153 (42.9152, -23.5937)
  point P154 (43.1734, -21.8721)
  point P155 (45.9529, -24.6516)
  point P156 (44.2313, -24.9098)
  point P157 (-21.786, -21.008)
  point P158 (-22.8571, -20.382)
  point P159 (-20.543, -18.0679)
  point P160 (-19.917, -19.139)
  point P161 (42.9133, 5.8238)
  point P162 (48.7552, 3.9417)
  point P163 (49.0496, 3.3)
  point P164 (49.3232, 1.8765)
  point P165 (43.6619, -6.0971)
  point P166 (40.4779, -2.9131)
  point P167 (-49.9781, 32.4)
  point P168 (-55.075, 27.3031)
  point P169 (-48.2811, 32.4)
  point P170 (-48.9332, -92.4)
  point P171 (-55.075, -87.9553)
  point P172 (-50.6303, -92.4)
  point P173 (-0.275, -28.3454)
  point P174 (-0.275, -27.214)
  point P175 (2.7082, -28.475)
  point P176 (-0.1454, -28.475)
  point P177 (6.0112, -23.475)
  point P178 (7.7082, -23.475)
  point P179 (21.5914, -25.5724)
  point P180 (21.5914, -23.8754)
  point P181 (29.9, -27.4077)
  point P182 (29.9, -26.842)
  point P183 (25.3004, -20.1664)
  point P184 (26.9974, -20.1664)
  point P185 (29.9, 0.4138)
  point P186 (29.9, -1.2832)
  point P187 (28.5832, -2.6)
  point P188 (26.8862, -2.6)
  point P189 (29.9, 20.5341)
  point P190 (29.9, 21.9484)
  point P191 (23.3734, 28.475)
  point P192 (27.697, 28.475)
  point P193 (21.5914, 24.0665)
  point P194 (3.988, 23.575)
  point P195 (4.925, 24.512)
  point P196 (-21.0827, 23.575)
  point P197 (-20.517, 23.575)
  point P198 (-22.1414, 26.5784)
  point P199 (-20.2448, 28.475)
  dimension "d198" = 1
  dimension "d199" = 1.2
  dimension "d202" = 45
  dimension "d204" = 12.5
  dimension "d215" = 11.3
  dimension "d218" = 11.3
  constraints: 2050 end point, 11 perpendicular, 2 point on line, 1 collinear, 2049 other
  measures "d199" distance between parallel lines of L18 L21
  measures "d202" angle of L5 L25
  measures "d204" distance between parallel lines of L17 L19
  measures "d215" distance of L21.end L26.start
  measures "d218" distance of L21.end L82.start
extrude "Extrusion16" add sketch "Sketch21" along normal blind 1 contours A1 L128 L126 L127 L129 L1 L130 L131 L16 L252 L250 L249 L248 L246 L247 L368 L366 L365 L364 L362 L363 L484 L482 L481 L480 L478 L479 L600 L598 L597 L596 L594 L595 L716 L714 L713 L712 L710 L711 L832 L830 L829 L828 L13 L707 L709 L708 L706 L705 L704 L583 L585 L584 L582 L581 L580 L459 L461 L460 L458 L457 L456 L335 L337 L336 L334 L333 L332 L211 L213 L212 L210 L209 L208 L87 L89 L88 L19 L27 L29 L28 L147 L149 L148 L14 L267 L269 L391 L393 L515 L517 L639 L641 L763 L765 L887 L889 L890 L891 L893 L15 L894 L895 L776 L774 L775 L777 L778 L779 L1057 L660 L658 L1054 L659 A8 L540 L538 L539 L541 L542 L543 L545 L1083 L1084 L546 L547 L428 L426 L427 L429 L1082 L1081 L430 L431 L312 L310 L311 L313 L314 L315 L196 L194 L195 A7 L76 L74 L75 L136 L134 L133 L132 A0 L71 L73 L72 L70 L69 L68 L66 L67 | L77 A7 L78 L16 | L80 A7 L199 L16 | L197 L15 L198 A7 | L15 L312 L1081 L431 | L430 L1081 L1082 L429 L15 | L15 L544 A8 L663 | L662 A8 L661 L15 | L1084 L1083 L545 | L15 L660 L1056 L779 | L1056 L660 L1057 L779 | L15 L892 L14 L1011 | L658 L1054 L1057 | L14 L146 L18 L145 | L1046 L1049 L650 L651 L532 L530 L1048 L1047 L529 L528 | L18 L19 L20 L13 L23 L24 L21 L14 | L526 L527 L1043 L408 L406 L1042 L1045 L405 L404 L1044 | L14 L22 L13 L17 | L1049 L651 L650 | L13 L85 L20 L86 | L1053 L1052 L656 L654 L1051 L1050 L653 L652 | L286 L1064 L285 L1061 L1062 L1058 | L1062 L1061 L285 L1059 | L183 L1076 L64 L8 | L183 L1077 L64 L1076 | L59 L1075 L120 L8 | L10 L52 L1068 L171 | L118 L1074 L1073 L117 L10 L9 L8 | L1068 L52 L1067 L171 | L10 L116 L1071 L1072 L55 | L1072 L1071 L116 L1069 L55
sketch "Sketch22" plane through (0, 1.6, 0) normal (0, 1, 0) x (1, 0, 0)
  line L0 (-56.075, 33.4) -> (-56.075, -93.4) projected
  line L1 (-56.075, -93.4) -> (60.725, -93.4) projected
  line L2 (60.725, 33.4) -> (-56.075, 33.4) projected
  line L3 (60.725, -93.4) -> (60.725, 33.4) projected
  line L4 (-55.075, -92.4) -> (-55.075, 32.4)
  line L5 (-55.075, 32.4) -> (59.725, 32.4)
  line L6 (59.725, 32.4) -> (59.725, -92.4)
  line L7 (59.725, -92.4) -> (-55.075, -92.4)
  point P0 (0, 0)
  dimension "d223" = 1
  constraints: 8 end point, 3 other
  measures "d223" distance between parallel lines of L0 L4
extrude "Extrusion17" add sketch "Sketch22" along normal blind 1
sketch "Sketch23" plane through (0, 1.6, 0) normal (0, 1, 0) x (1, 0, 0)
  line L0 (-50.135, -88.65) -> (34.865, -88.65)
  line L1 (34.865, -88.65) -> (34.865, -35.65)
  line L2 (34.865, -35.65) -> (-50.135, -35.65)
  line L3 (-50.135, -35.65) -> (-50.135, -88.65)
  line L4 (-56.075, 33.4) -> (-56.075, -93.4) projected
  line L5 (-56.075, -93.4) -> (60.725, -93.4) projected
  point P0 (0, 0)
  dimension "d228" = 53
  dimension "d229" = 85
  dimension "d243" = 5.94
  dimension "d244" = 4.75
  constraints: 8 end point, 2 parallel, 1 horizontal, 1 perpendicular
  measures "d228" distance between parallel lines of L0 L2
  measures "d229" distance between parallel lines of L3 L1
  measures "d243" distance between parallel lines of L4 L3
  measures "d244" distance between parallel lines of L5 L0
extrude "Extrusion18" add sketch "Sketch23" along normal blind 6.1
sketch "Sketch25" plane through (0, 1.6, 0) normal (0, 1, 0) x (1, 0, 0)
  arc A0 (21.3929, 22.1709) -> (22.4041, 23.1821) centre (22.95, 21.625) ccw projected
  circle A1 centre (22.95, 21.625) radius 2.85
  arc A2 (-21.786, -21.008) -> (-19.917, -19.139) centre (-21.55, -19.375) ccw projected
  arc A3 (-22.8571, -20.382) -> (-21.786, -21.008) centre (-21.55, -19.375) ccw projected
  arc A4 (-20.543, -18.0679) -> (-22.8571, -20.382) centre (-21.55, -19.375) ccw projected
  arc A5 (-19.917, -19.139) -> (-20.543, -18.0679) centre (-21.55, -19.375) ccw projected
  circle A6 centre (-3.05, -21.875) radius 1.65 projected
  circle A7 centre (-3.05, -21.875) radius 2.75
  circle A8 centre (-21.55, -19.375) radius 2.75
  point P0 (0, 0)
  point P1 (-2.6469, -23.475)
  point P2 (-3.4531, -23.475)
  dimension "d245" = 5.7
  dimension "d246" = 5.5
  dimension "d247" = 5.5
  constraints: 3 centre point, 3 coincident
  measures "d245" diameter of A1
  measures "d246" diameter of A7
  measures "d247" diameter of A8
extrude "Extrusion20" cut sketch "Sketch25" along normal through all contours A1 | A6 | A7 | A8
sketch "Sketch30" plane through (0, 0, 0) normal (0, -1, 0) x (1, 0, 0)
  line L0 (-56.075, -33.4) -> (-56.075, 93.4) projected
  line L1 (-57.675, 27.5) -> (-56.075, 27.5)
  line L2 (-56.075, 27.5) -> (-56.075, 32.5)
  line L3 (-56.075, 32.5) -> (-57.675, 32.5)
  line L4 (-57.675, 32.5) -> (-57.675, 27.5)
  point P0 (0, 0)
  point P1 (-56.075, 30)
  dimension "d271" = 5
  dimension "d272" = 1.6
  constraints: 8 end point, 2 midpoint, 2 parallel, 1 horizontal, 1 perpendicular
  measures "d271" distance of L3.end L1.start
  measures "d272" distance between parallel lines of L4 L0
extrude "Extrusion22" add sketch "Sketch30" against normal blind 2.6
fillet "Fillet3" radius 0.4 6 edges at (60.725, 1.3, 93.4) (60.725, 1.3, -33.4) (-56.075, 1.3, -33.4) (-56.075, 1.3, 93.4) (-57.675, 1.3, 27.5) (-57.675, 1.3, 32.5)
sketch "Sketch33" plane through (0, 0, 0) normal (0, -1, 0) x (1, 0, 0)
  arc A0 (-57.275, 32.5) -> (-57.675, 32.1) centre (-57.275, 32.1) ccw projected
  line L0 (-57.675, 32.1) -> (-57.675, 27.9) projected
  arc A1 (-57.675, 27.9) -> (-57.275, 27.5) centre (-57.275, 27.9) ccw projected
  line L1 (-57.275, 27.5) -> (-56.075, 27.5) projected
  line L2 (-56.075, -33) -> (-56.075, 27.5) projected
  arc A2 (-56.075, -33) -> (-55.675, -33.4) centre (-55.675, -33) ccw projected
  line L3 (60.325, -33.4) -> (-55.675, -33.4) projected
  arc A3 (60.325, -33.4) -> (60.725, -33) centre (60.325, -33) ccw projected
  line L4 (60.725, 93) -> (60.725, -33) projected
  arc A4 (60.725, 93) -> (60.325, 93.4) centre (60.325, 93) ccw projected
  line L5 (-55.675, 93.4) -> (60.325, 93.4) projected
  arc A5 (-55.675, 93.4) -> (-56.075, 93) centre (-55.675, 93) ccw projected
  line L6 (-56.075, 32.5) -> (-56.075, 93) projected
  line L7 (-56.075, 32.5) -> (-57.275, 32.5) projected
  arc A6 (-41.925, 1.75) -> (-41.925, -1.75) centre (-41.925, 0) ccw projected
  line L8 (-41.925, 1.75) -> (-38.425, 1.75) projected
  arc A7 (-38.425, -1.75) -> (-38.425, 1.75) centre (-38.425, 0) ccw projected
  line L9 (-38.425, -1.75) -> (-41.925, -1.75) projected
  line L10 (43.075, -1.75) -> (43.075, 1.75) projected
  arc A8 (46.575, 1.75) -> (43.075, 1.75) centre (44.825, 1.75) ccw projected
  line L11 (46.575, 1.75) -> (46.575, -1.75) projected
  arc A9 (43.075, -1.75) -> (46.575, -1.75) centre (44.825, -1.75) ccw projected
  line L12 (24.9, 23.238) -> (24.9, -16.164) projected
  arc A10 (24.9, -16.164) -> (18.9, -17.475) centre (22.95, -21.625) ccw projected
  line L13 (18.9, -17.475) -> (0, -17.475) projected
  line L14 (0, -17.475) -> (0, 23.475) projected
  line L15 (0, 23.475) -> (24.663, 23.475) projected
  line L16 (24.663, 23.475) -> (24.9, 23.238) projected
  line L17 (-0.875, -33.4) -> (5.525, -33.4)
  line L18 (5.525, -33.4) -> (5.525, -31.4)
  line L19 (5.525, -31.4) -> (-0.875, -31.4)
  line L20 (-0.875, -31.4) -> (-0.875, -33.4)
  line L21 (-0.875, 91.4) -> (5.525, 91.4)
  line L22 (5.525, 91.4) -> (5.525, 93.4)
  line L23 (5.525, 93.4) -> (-0.875, 93.4)
  line L24 (-0.875, 93.4) -> (-0.875, 91.4)
  line L25 (58.725, 26.8) -> (60.725, 26.8)
  line L26 (60.725, 26.8) -> (60.725, 33.2)
  line L27 (60.725, 33.2) -> (58.725, 33.2)
  line L28 (58.725, 33.2) -> (58.725, 26.8)
  point P0 (0, 0)
  point P1 (2.325, -33.4)
  point P2 (60.725, 30)
  point P3 (2.325, 93.4)
  dimension "d291" = 6.4
  dimension "d292" = 6.4
  dimension "d293" = 6.4
  dimension "d294" = 2
  dimension "d295" = 2
  dimension "d296" = 2
  constraints: 24 end point, 6 midpoint, 6 parallel, 3 horizontal, 3 perpendicular
  measures "d291" distance of L18.end L19.end
  measures "d292" distance of L21.start L21.end
  measures "d293" distance of L27.end L25.start
  measures "d294" distance between parallel lines of L3 L19
  measures "d295" distance of L26.end L27.end
  measures "d296" distance of L23.end L21.start
extrude "Extrusion25" cut sketch "Sketch33" against normal blind 0.8 contours L5 L22 L21 L24 | L20 L19 L18 L3 | L4 L25 L28 L27
chamfer "Chamfer8" distance 0.4 angle 45 34 edges at (32.925, 0, 93.4) (60.6078, 0, 93.2828) (60.725, 0, 63.1) (-28.275, 0, 93.4) (-55.9578, 0, 93.2828) (-56.075, 0, 62.75) (60.725, 0, -3.1) (60.6078, 0, -33.2828) (32.925, 0, -33.4) (-28.275, 0, -33.4) (-55.9578, 0, -33.2828) (-56.075, 0, -2.75) (-40.175, 0, 1.75) (-36.675, 0, 0) (-40.175, 0, -1.75) (-43.675, 0, 0) (43.075, 0, 0) (44.825, 0, 3.5) (46.575, 0, 0) (44.825, 0, -3.5) (-56.675, 0, 27.5) (-57.5578, 0, 27.6172) (-57.675, 0, 30) (-57.5578, 0, 32.3828) (-56.675, 0, 32.5) (2.325, 0, -31.4) (-0.875, 0, -32.4) (5.525, 0, -32.4) (59.725, 0, 26.8) (58.725, 0, 30) (59.725, 0, 33.2) (5.525, 0, 92.4) (2.325, 0, 91.4) (-0.875, 0, 92.4)
equation "\"d3\" = topbot"
equation "\"d20\" = walls"
equation "\"d17\" = topbot"
equation "\"walls\" = 1.6"
equation "\"topbot\" = 1.6"
equation "\"insertsD\" = 4.6"
equation "\"d35\" = 4.6"
equation "\"d40\" = 4.6"
body "Solid1"
